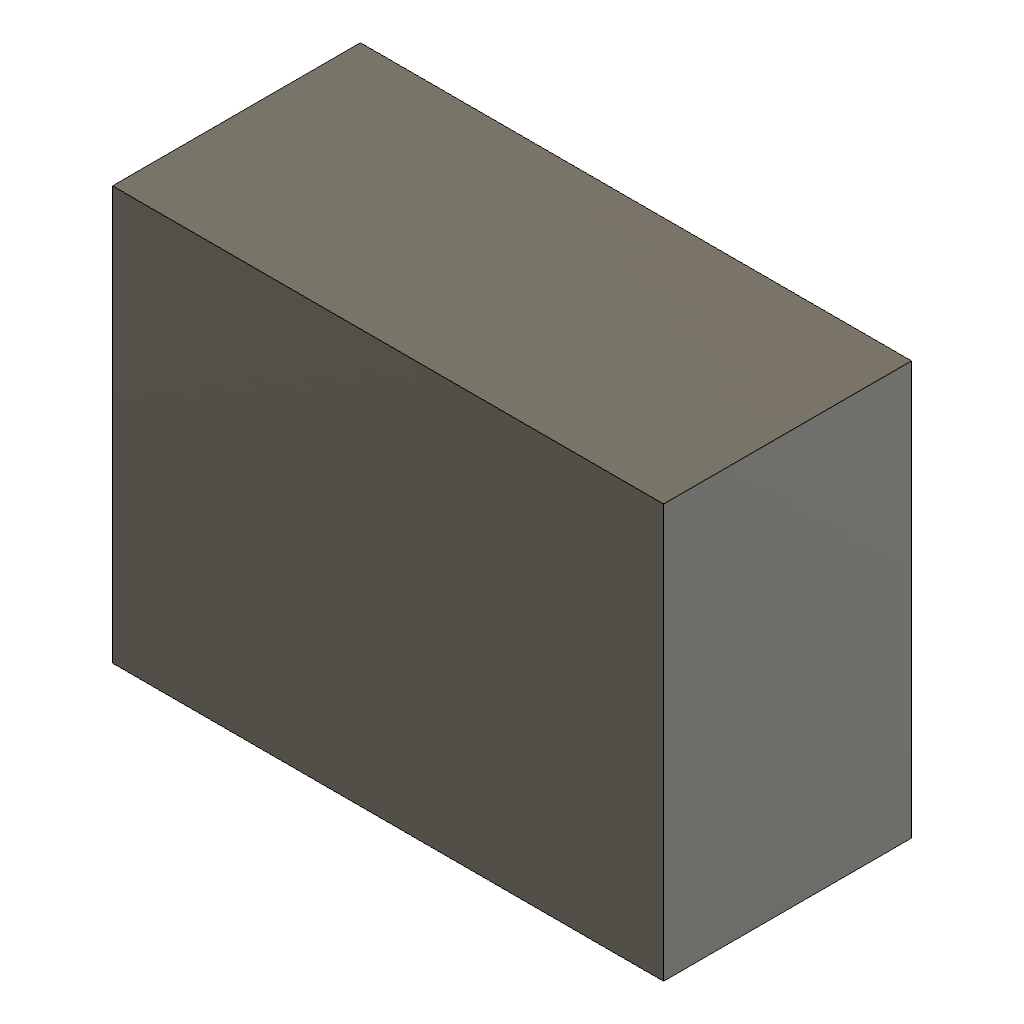
offset_negative (Autodesk Fusion 360 design; units mm, degrees)
part number: 2026-10-20-20-19-11-442
Autodesk Fusion 360 part; units mm, degrees
sketch "Sketch1" plane through (0, 0, 0) normal (0, 0, 1) x (1, 0, 0)
  line L0 (0, 0) -> (40, 0)
  line L1 (40, 0) -> (40, 30)
  line L2 (40, 30) -> (0, 30)
  line L3 (0, 30) -> (0, 0)
extrude "FaceEditSeed" add sketch "Sketch1" along normal blind 20
move_face "ProbeFaceEdit" offset -2 1 faces at (13.3333, 20, 20)
